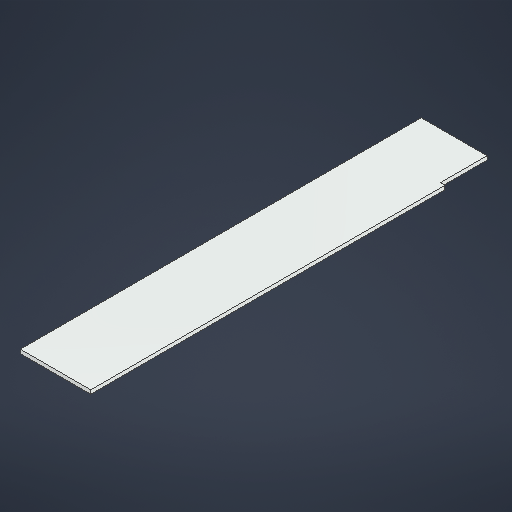
# Autodesk Inventor part: enclosure_side
Saved by Autodesk Inventor 2026.2 (Build 302298010, 298A)
## iProperties
Created: 2026-09-14
Part Number: enclosure_side
Material: Generic
Document SubType Name: Modeling
Designer: grady
Density: 1 g/cm^3
Appearance: Default
Author: grady
Autodesk Inventor part; units mm, degrees
ref_plane "YZ Plane" through (0, 0, 0) normal (1, 0, 0) x (0, 1, 0)
ref_plane "XZ Plane" through (0, 0, 0) normal (0, 1, 0) x (-1, 0, 0)
ref_plane "XY Plane" through (0, 0, 0) normal (0, 0, 1) x (1, 0, 0)
sketch "Sketch1" plane through (0, 0, 0) normal (0, 1, 0) x (-1, 0, 0)
  line L0 (23, 131) -> (-23, 131)
  line L1 (-23, 131) -> (-23, -100.5)
  line L2 (-20, -131) -> (23, -131)
  line L3 (23, -131) -> (23, 131)
  line L4 (23, 131) -> (-23, -131) construction
  line L5 (-23, 131) -> (23, -131) construction
  line L6 (-23, -100.5) -> (-20, -100.5)
  line L7 (-20, -100.5) -> (-20, -131)
  point P0 (0, 0)
  dimension "d0" = 46
  dimension "d1" = 262
  dimension "d2" = 30.5
  dimension "d3" = 3
  constraints: 16 end point, 2 midpoint, 2 parallel, 2 perpendicular, 1 horizontal
  measures "d0" distance of L2.end L4.end
  measures "d1" distance of L4.end L0.end
  measures "d2" distance of L1.end L4.end
  measures "d3" distance of L1.end L6.end
extrude "Extrusion1" add sketch "Sketch1" along normal blind 2.5
body "Solid1"
